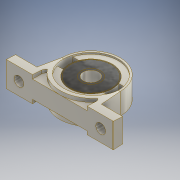
# Autodesk Inventor part: 8mmVerticalLeadMountingShaftSupportBearing
Saved by Autodesk Inventor 2017 (Build 210142000, 142)
## iProperties
Part Number: 8mmVerticalLeadMountingShaftSupportBearing
Material: Aluminio
Document SubType Name: Modeling
Designer: Jaime
Density: 2.7 g/cm^3
Appearance: Titanio
Author: Jaime
Autodesk Inventor part; units mm, degrees
ref_plane "YZ Plane" through (0, 0, 0) normal (1, 0, 0) x (0, 1, 0)
ref_plane "XZ Plane" through (0, 0, 0) normal (0, 1, 0) x (-1, 0, 0)
sketch "Boceto2" plane through (0, 0, 0) normal (0, 0, 1) x (1, 0, 0)
  line L0 (-27.5, -2.5) -> (27.5, -2.5)
  line L1 (27.5, -2.5) -> (27.5, 2.5)
  line L2 (27.5, 2.5) -> (-27.5, 2.5)
  line L3 (-27.5, 2.5) -> (-27.5, -2.5)
  line L4 (-27.5, -2.5) -> (27.5, 2.5) construction
  line L5 (27.5, -2.5) -> (-27.5, 2.5) construction
  point P0 (0, 0)
  dimension "d26" = 55
  dimension "d27" = 5
  constraints: 12 end point, 2 midpoint, 2 parallel, 1 horizontal, 1 perpendicular
  measures "d26" distance of L2.end L1.end
  measures "d27" distance of L1.end L0.end
extrude "Extrusión1" add sketch "Boceto2" along normal mid plane 13
sketch "Boceto3" plane through (0, 0, 6.5) normal (0, 0, 1) x (1, 0, 0)
  line L0 (-27.5, -2.5) -> (27.5, -2.5) construction
  line L1 (0, -2.5) -> (0, 13.5) construction
  line L2 (0, -2.5) -> (16, -2.5) construction
  circle A0 centre (0, 13.5) radius 4
  circle A1 centre (0, 13.5) radius 15
  point P0 (0, 0)
  dimension "d30" = 16
  dimension "d31" = 90
  dimension "d32" = 8
  dimension "d33" = 30
  constraints: 4 end point, 2 centre point, 2 coincident, 2 perpendicular, 1 horizontal, 1 midpoint
  measures "d30" distance of L1.start L1.end
  measures "d31" angle of L2 L1
  measures "d32" diameter of A0
  measures "d33" diameter of A1
extrude "Extrusión2" add sketch "Boceto3" against normal blind 13
sketch "Boceto4" plane through (0, 0, 6.5) normal (0, 0, 1) x (1, 0, 0)
  circle A0 centre (0, 13.5) radius 4 construction
  line L0 (-10.198, 2.5) -> (-27.5, 2.5) construction
  line L1 (-27.5, 2.5) -> (-27.5, -2.5) construction
  line L2 (-27.5, -2.5) -> (27.5, -2.5) construction
  line L3 (27.5, -2.5) -> (27.5, 2.5) projected
  line L4 (27.5, 2.5) -> (10.198, 2.5) construction
  arc A1 (10.198, 2.5) -> (-10.198, 2.5) centre (0, 13.5) ccw construction
  line L5 (4, 13.5) -> (15, 13.5) construction
  line L6 (4, 13.5) -> (15, 13.5) construction
  line L7 (15, 13.5) -> (15, 2.5) construction
  line L8 (0, 0) -> (0, 30) construction
  line L9 (0, 0) -> (30, 0) construction
  line L10 (15, 2.5) -> (16.5, 2.5)
  line L11 (10.198, 2.5) -> (27.5, 2.5) projected
  line L12 (15, 2.5) -> (16.5, 2.5) construction
  line L13 (16.5, 2.5) -> (15, 13.5)
  line L14 (-16.5, 2.5) -> (-15, 13.5)
  line L15 (-16.5, 2.5) -> (15, 2.5)
  arc A2 (-4, 13.5) -> (4, 13.5) centre (0, 13.5) ccw
  line L16 (-15, 13.5) -> (-4, 13.5)
  line L17 (4, 13.5) -> (15, 13.5)
  dimension "d36" = 15
  dimension "d37" = 0
  dimension "d38" = 11
  dimension "d39" = 90
  dimension "d40" = 30
  dimension "d41" = 90
  dimension "d42" = 1.5
  dimension "d43" = 0
  dimension "d44" = 8
  dimension "d45" = 97.765
  constraints: 24 end point, 6 horizontal, 2 collinear, 2 equal length, 2 point on circle, 2 symmetric about line, 1 centre point, 1 coincident, 1 perpendicular, 1 tangent, 1 vertical
  measures "d36" distance of A1.centre L5.end
  measures "d37" distance between parallel lines of L5 L6
  measures "d38" distance of L5.end L7.end
  measures "d39" angle of L5 L7
  measures "d40" distance of L8.start L8.end
  measures "d41" angle of L9 L8
  measures "d42" distance of L7.end L10.end
  measures "d43" distance between parallel lines of L10 L12
  measures "d44" diameter of A2
  measures "d45" angle of L4 L13
extrude "Extrusión3" add sketch "Boceto4" against normal blind 13
sketch "Boceto6" plane through (27.5, -2.5, 6.5) normal (1, 0, 0) x (0, 0, -1)
  line L0 (13, 0) -> (0, 0) projected
  line L1 (0, 16) -> (0, 31) projected
  line L2 (0, 0) -> (0, 31)
  line L3 (0, 31) -> (1, 31)
  line L4 (0, 31) -> (13, 31) projected
  line L5 (0, 31) -> (1, 31) construction
  line L6 (1, 31) -> (1, 16)
  line L7 (0, 0) -> (1, 16)
  line L8 (6.5, 2.5) -> (6.5, 22.5) construction
  line L9 (6.5, 2.5) -> (26.5, 2.5) construction
  line L10 (0, 0) -> (13, 0)
  line L11 (13, 16) -> (13, 31)
  line L12 (13, 0) -> (13, 31)
  line L13 (13, 31) -> (12, 31)
  line L14 (13, 31) -> (0, 31)
  line L15 (13, 31) -> (12, 31) construction
  line L16 (12, 31) -> (12, 16)
  line L17 (13, 0) -> (12, 16)
  dimension "d55" = 1
  dimension "d56" = 0
  dimension "d57" = 15
  dimension "d58" = 90
  dimension "d59" = 20
  dimension "d60" = 90
  constraints: 30 end point, 9 symmetric about line, 2 equal length, 2 horizontal, 2 vertical, 1 collinear, 1 perpendicular
  measures "d55" distance of L1.end L3.end
  measures "d56" distance between parallel lines of L3 L5
  measures "d57" distance of L3.end L6.end
  measures "d58" angle of L3 L6
  measures "d59" distance of L8.start L8.end
  measures "d60" angle of L9 L8
extrude "Extrusión4" cut sketch "Boceto6" against normal blind 55 contours L17 L16 L4 L11 L12 | L2 L1 L3 L6 L7
ref_plane "Plano de trabajo1" through (0, 0, 6.5) normal (0, 0, 1) x (1, 0, 0)
sketch "Boceto9" plane through (0, 0, 6.5) normal (0, 0, 1) x (1, 0, 0)
  line L0 (0, 0) -> (0, -2.5) construction
  line L1 (27.5, -2.5) -> (-27.5, -2.5) construction
  line L2 (0, -2.5) -> (0, 13.5) construction
  line L3 (0, -2.5) -> (16, -2.5) construction
  circle A0 centre (0, 13.5) radius 14
  dimension "d65" = 16
  dimension "d66" = 90
  dimension "d67" = 28
  constraints: 6 end point, 1 centre point, 1 coincident, 1 horizontal, 1 midpoint, 1 perpendicular, 1 vertical
  measures "d65" distance of L0.end L2.end
  measures "d66" angle of L3 L2
  measures "d67" diameter of A0
extrude "Extrusión5" cut sketch "Boceto9" against normal blind 1.8
mirror "Simetría1" about plane through (0, 0, 0) normal (0, 0, 1) of "Extrusión5"
sketch "Boceto10" plane through (-27.5, -2.5, 6.5) normal (0, -1, 0) x (1, 0, 0)
  line L0 (6.5, -8) -> (48.5, -8) construction
  line L1 (48.5, -8) -> (48.5, -5) construction
  line L2 (48.5, -5) -> (6.5, -5) construction
  line L3 (6.5, -5) -> (6.5, -8) construction
  line L4 (6.5, -8) -> (48.5, -5) construction
  line L5 (48.5, -8) -> (6.5, -5) construction
  circle A0 centre (48.5, -6.5) radius 2.5
  circle A1 centre (6.5, -6.5) radius 2.5
  point P0 (27.5, -6.5)
  dimension "d70" = 42
  dimension "d71" = 3
  dimension "d72" = 5
  dimension "d73" = 5
  constraints: 12 end point, 4 midpoint, 2 centre point, 2 parallel, 1 horizontal, 1 perpendicular
  measures "d70" distance of L2.end L1.end
  measures "d71" distance of L1.end L0.end
  measures "d72" diameter of A0
  measures "d73" diameter of A1
extrude "Extrusión6" cut sketch "Boceto10" against normal up to next
sketch "Boceto11" plane through (0, 13.5, 4.7) normal (0, 0, 1) x (1, 0, 0)
  circle A0 centre (0, 0) radius 4 projected
  circle A1 centre (0, 0) radius 14 construction
  circle A2 centre (0, 0) radius 14 construction
  line L0 (-15, -4) -> (15, 4) construction
  line L1 (15, -4) -> (-15, 4) construction
  arc A3 (-10.247, 4) -> (-10.247, -4) centre (0, 0) ccw
  arc A4 (10.247, -4) -> (10.247, 4) centre (0, 0) ccw
  line L2 (-13.4164, -4) -> (-10.247, -4)
  line L3 (10.247, -4) -> (13.4164, -4)
  line L4 (13.4164, 4) -> (10.247, 4)
  line L5 (-10.247, 4) -> (-13.4164, 4)
  arc A5 (-13.4164, 4) -> (-13.4164, -4) centre (0, 0) ccw
  arc A6 (13.4164, -4) -> (13.4164, 4) centre (0, 0) ccw
  dimension "d78" = 28
  dimension "d82" = 11
  dimension "d83" = 11
  dimension "d84" = 14.931
  dimension "d85" = 14.931
  dimension "d86" = 8
  dimension "d87" = 0
  dimension "d88" = 8
  dimension "d89" = 0
  dimension "d90" = 8
  dimension "d91" = 0
  dimension "d92" = 14
  dimension "d93" = 14
  constraints: 12 end point, 12 point on circle, 5 centre point, 4 parallel, 2 coincident, 2 horizontal, 2 midpoint, 2 tangent
  measures "d78" diameter of A2
  measures "d82" radius of A4
  measures "d83" radius of A3
  measures "d84" angle of L0 L3
  measures "d85" angle of L1 L3
  measures "d86" distance between parallel lines of L4 L3
  measures "d87" distance between parallel lines of L3 L2
  measures "d88" distance from line of L0.end L3
  measures "d89" distance from line of L1.start L3
  measures "d90" distance from line of L1.end L3
  measures "d91" distance from line of L0.start L3
  measures "d92" radius of A5
  measures "d93" radius of A6
extrude "Extrusión7" cut sketch "Boceto11" against normal blind 3.5 contours A3 L2 A5 L5 | A4 L4 A6 L3
sketch "Boceto12" plane through (0, 13.5, -4.7) normal (0, 0, -1) x (-1, 0, 0)
  circle A0 centre (0, 0) radius 4 projected
  circle A1 centre (0, 0) radius 4
  circle A2 centre (0, 0) radius 5
  point P0 (0, -13.5)
  dimension "d96" = 8
  dimension "d97" = 10
  constraints: 2 centre point, 2 coincident
  measures "d96" diameter of A1
  measures "d97" diameter of A2
extrude "Extrusión8" add sketch "Boceto12" along normal blind 4
sketch "Boceto13" plane through (0, 0, 6.5) normal (0, 0, 1) x (1, 0, 0)
  arc A0 (-14, 13.5) -> (14, 13.5) centre (0, 13.5) ccw construction
  line L0 (-14, 13.5) -> (-15, 13.5) construction
  line L1 (-16.5, 2.5) -> (-15, 13.5) construction
  line L2 (-27.5, 2.5) -> (-16.5, 2.5) construction
  line L3 (-27.5, -2.5) -> (-27.5, 2.5) construction
  line L4 (-27.5, -2.5) -> (27.5, -2.5) construction
  line L5 (27.5, 2.5) -> (27.5, -2.5) construction
  line L6 (16.5, 2.5) -> (27.5, 2.5) construction
  line L7 (15, 13.5) -> (16.5, 2.5) construction
  line L8 (15, 13.5) -> (14, 13.5) construction
  line L9 (27.5, -2.5) -> (-27.5, -2.5) projected
  line L10 (0, -2.5) -> (14, -2.5)
  line L11 (0, -2.5) -> (14, -2.5) construction
  line L12 (14, -2.5) -> (14, 2.5) construction
  line L13 (-14, 2.0266) -> (-14, -2.5)
  line L14 (-14, -2.5) -> (0, -2.5)
  line L15 (-14, -2.5) -> (13.8905, -2.5)
  line L16 (13.8905, -2.5) -> (13.8905, 2.0316)
  line L17 (-14, 2.0266) -> (-14, -2.5)
  arc A1 (-12.9294, 4.0777) -> (-14, 2.0266) centre (-11.5, 2.0266) ccw
  arc A2 (13.8905, 2.0316) -> (12.8939, 4.0291) centre (11.3905, 2.0316) ccw
  arc A3 (-12.9294, 4.0777) -> (12.8939, 4.0291) centre (0, 13.4962) ccw
  point P0 (0, 0)
  point P1 (-14, 2.5)
  point P2 (13.8905, 4.5)
  dimension "d102" = 14
  dimension "d103" = 0
  dimension "d104" = 5
  dimension "d105" = 90
  dimension "d106" = 28
  dimension "d108" = 5
  dimension "d110" = 28
  dimension "d111" = 7
  dimension "d112" = 2.5
  dimension "d113" = 2.5
  dimension "d114" = 15.9962
  dimension "d115" = 13.6095
  dimension "d116" = 4.5316
  constraints: 20 end point, 7 point on circle, 4 tangent, 3 centre point, 3 perpendicular, 2 collinear, 2 horizontal, 2 point on line, 1 midpoint, 1 parallel
  measures "d102" distance of L10.start L10.end
  measures "d103" distance between parallel lines of L11 L10
  measures "d104" distance of L10.end L12.end
  measures "d105" angle of L12 L10
  measures "d106" distance of L12.end point (-14, 2.5)
  measures "d108" distance of point (-14, 2.5) L13.end
  measures "d110" distance of L13.start point (13.891, 4.5)
  measures "d111" distance of point (13.891, 4.5) L15.end
  measures "d112" radius of A1
  measures "d113" radius of A2
  measures "d114" radius of A3
  measures "d115" distance between parallel lines of L5 L16
  measures "d116" distance from line of L16.end L9
extrude "Extrusión9" cut sketch "Boceto13" against normal blind 2 contours L9 L13 A1 A3
mirror "Simetría2" about plane through (0, 0, 0) normal (1, 0, 0) of "Extrusión9"
mirror "Simetría3" about plane through (0, 0, 0) normal (0, 0, 1) of "Extrusión9", "Simetría2"
sketch "Boceto14" plane through (0, 0, 4.7) normal (0, 0, 1) x (1, 0, 0)
  line L0 (-10.247, 9.5) -> (-13.4164, 9.5) projected
  arc A0 (-13.4164, 9.5) -> (13.4164, 9.5) centre (0, 13.5) ccw projected
  line L1 (13.4164, 9.5) -> (10.247, 9.5) projected
  arc A1 (10.247, 9.5) -> (10.247, 17.5) centre (0, 13.5) ccw projected
  line L2 (10.247, 17.5) -> (13.4164, 17.5) projected
  arc A2 (13.4164, 17.5) -> (-13.4164, 17.5) centre (0, 13.5) ccw projected
  line L3 (-13.4164, 17.5) -> (-10.247, 17.5) projected
  arc A3 (-10.247, 17.5) -> (-10.247, 9.5) centre (0, 13.5) ccw projected
  circle A4 centre (0, 13.5) radius 4 projected
  circle A5 centre (0, 13.5) radius 11
  circle A6 centre (0, 13.5) radius 10.5
  point P0 (0, 0)
  dimension "d119" = 22
  dimension "d120" = 21
  constraints: 2 centre point, 2 coincident
  measures "d119" diameter of A5
  measures "d120" diameter of A6
extrude "Extrusión10" add sketch "Boceto14" along normal blind 0.01 contours A3 A5 A1
mirror "Simetría4" about plane through (0, 0, 0) normal (0, 0, 1) of "Extrusión10"
sketch "Boceto15" plane through (0, 13.5, 4.7) normal (0, 0, 1) x (1, 0, 0)
  circle A0 centre (0, 0) radius 4 projected
  circle A1 centre (0, 0) radius 5
  circle A2 centre (0, 0) radius 4
  point P0 (0, -13.5)
  dimension "d123" = 10
  dimension "d124" = 8
  constraints: 2 centre point, 2 coincident
  measures "d123" diameter of A1
  measures "d124" diameter of A2
extrude "Extrusión11" add sketch "Boceto15" along normal blind 0.01
fillet "Empalme1" radius 0.25 9 edges at (22, 2.5, 6.1875) (27.5, 2.5, 0) (22, 2.5, -6.1875) (27.5, 0, -6.3438) (20.75, -2.5, -6.5) (-22, 2.5, -6.1875) (-27.5, 2.5, 0) (-22, 2.5, 6.1875) (27.5, -2.5, 0)
